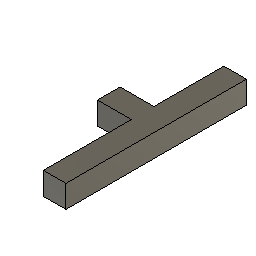
000a Full Robot (Autodesk Fusion 360 archive; units mm, degrees)
design "Top Piece"
Autodesk Fusion 360 part; units mm, degrees
sketch "Sketch1" plane through (0, 0, 0) normal (0, 0, 1) x (1, 0, 0)
  line L0 (0, -139.7) -> (0, -50.8)
  line L1 (-12.7, -50.8) -> (-12.7, -77.47)
  line L2 (-12.7, -90.17) -> (-12.7, -139.7)
  line L3 (-12.7, -90.17) -> (-31.75, -90.17)
  line L4 (-12.7, -77.47) -> (-31.75, -77.47)
  line L5 (-31.75, -90.17) -> (-31.75, -77.47)
  line L6 (-12.7, -50.8) -> (-12.7, -38.1)
  line L7 (-12.7, -38.1) -> (0, -38.1)
  line L8 (0, -38.1) -> (0, -50.8)
  line L9 (-12.7, -139.7) -> (0, -139.7)
  dimension "d7" = 19.05
  dimension "d8" = 19.05
  constraint vertical L0
  constraint perpendicular L2 L3
  constraint perpendicular L1 L4
  constraint perpendicular L4 L5
  constraint perpendicular L6 L7
  constraint perpendicular L0 L9
  measures "d7" distance of L2.start L3.end
  measures "d8" distance of L1.end L4.end
extrude "Extrude1" add sketch "Sketch1" along normal blind 12.7 makes body 1
copy_body "Body->Comp1" bodies 1 removing the originals makes body 2 in component "Component"
component "Component" placed x (1, 0, 0) y (0, 1, 0) z (0, 0, 1) at (0, 0, 0)

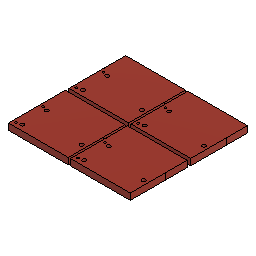
design "Gear_Motor_Base_Kevin"
Autodesk Fusion 360 part; units mm, degrees
sketch "Sketch2" plane through (0, 0, 0) normal (0, 0, 1) x (1, 0, 0)
  circle A0 centre (13.462, 0) radius 1.3075
  circle A1 centre (-23.8728, -9.6811) radius 0.7526
  circle A2 centre (-20.2417, -8.7123) radius 1.2943
  circle A3 centre (-20.2417, 8.7369) radius 1.2424
  circle A4 centre (-23.8726, 9.6996) radius 0.7649
  line L0 (-26.162, 11.1786) -> (-26.1614, 11.1786)
  line L1 (0, 0) -> (0, 0.4176)
  line L2 (-26.162, 0.0013) -> (-26.1613, 12.7013)
  line L3 (-26.162, 0.0013) -> (-26.162, -12.6987)
  line L4 (-26.162, -12.6987) -> (16.5915, -12.6998)
  line L5 (-26.1613, 12.7013) -> (16.5922, 12.7002)
  line L6 (16.5922, 12.7002) -> (16.5915, -12.6998)
  dimension "d23" = 12.7
  constraint coincident L1.start origin
  constraint perpendicular L0 L2
  constraint coincident L2 L0.end
  constraint perpendicular L4 L6
  measures "d23" distance of L2.start L2.end
extrude "Extrude2" add sketch "Sketch2" along normal blind 6.35 makes body 1
sketch "Sketch4" plane through (0, 0, 0) normal (0, 1, 0) x (1, 0, 0)
  circle A0 centre (57.912, -2.54) radius 1.1811
  circle A1 centre (37.592, -2.54) radius 1.1811
  dimension "d26" = 2.3622
  dimension "d27" = 2.3622
  dimension "d28" = 20.32
  measures "d26" diameter of A0
  measures "d27" diameter of A1
  measures "d28" distance of A0.centre A1.centre
extrude "Extrude4" cut 1 faces at (-8.6811, 0.0157, 6.35) along direction (0, 0, -1) blind 1.778 on bodies 1 bodies 1
extrude "Extrude5" add 1 faces at (-11.9102, 12.7009, 1.524) along direction (0.000026, 1, 0) blind 15.24 on bodies 1 bodies 1
move_body "Move2" bodies 1 to x (1, 0, 0) y (0, 1, 0) z (0, 0, 1) at (-17.3889, 13.7662, 0)
copy_body "CopyPasteBodies2" bodies 1 makes body 2
move_body "Move3" bodies 2 to x (1, 0, 0) y (0, 1, 0) z (0, 0, 1) at (0.1663, 43.0831, 0)
copy_body "CopyPasteBodies3" bodies 2 1 makes body 3 makes body 4
move_body "Move4" bodies 3 4 to x (1, 0, 0) y (0, 1, 0) z (0, 0, 1) at (-44.241, -0.152, 0)

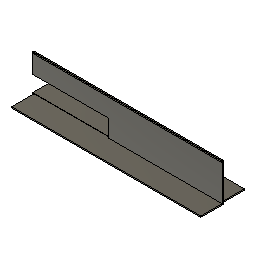
design "SideParts"
Autodesk Fusion 360 part; units mm, degrees
sketch "Sketch1" plane through (0, 0, 0) normal (1, 0, 0) x (0, 1, 0)
  line L0 (0, 0) -> (0, 39.37)
  line L1 (0, 39.37) -> (1.27, 39.37)
  line L2 (1.27, 39.37) -> (1.27, 0)
  line L3 (1.27, 0) -> (0, 0)
  line L4 (1.27, 0) -> (24.13, 0)
  line L5 (24.13, 0) -> (24.13, 1.27)
  line L6 (24.13, 1.27) -> (1.27, 1.27)
  line L7 (52.07, 0) -> (52.07, 1.27)
  line L8 (74.93, 0) -> (76.2, 0)
  line L9 (74.93, 0) -> (52.07, 0)
  line L10 (74.93, 39.37) -> (74.93, 0)
  line L11 (76.2, 39.37) -> (74.93, 39.37)
  line L12 (76.2, 0) -> (76.2, 39.37)
  line L13 (52.07, 1.27) -> (74.93, 1.27)
  point P0 (76.2, 0)
  dimension "d1" = 39.37
  dimension "d2" = 22.86
  constraint coincident L0.start L3.end
  constraint vertical L0
  constraint perpendicular L0 L1
  constraint perpendicular L1 L2
  constraint perpendicular L0 L3
  constraint perpendicular L2 L4
  constraint perpendicular L4 L5
  constraint coincident L2 L6.end
  constraint perpendicular L2 L6
  measures "d1" distance of L0.start L0.end
  measures "d2" distance of L2.end L4.end
extrude "Extrude1" add sketch "Sketch1" along normal blind 203.2 makes body 1 at (67.7333, 76.2, 13.1233) makes body 2 at (67.7333, 0, 13.1233)
sketch "Sketch2" plane through (0, 1.27, 0) normal (0, 1, 0) x (-1, 0, 0)
  line L0 (0, 1.27) -> (0, 39.37)
  line L1 (0, 39.37) -> (-203.2, 39.37)
  line L2 (-203.2, 39.37) -> (-203.2, 1.27)
  line L3 (-203.2, 1.27) -> (0, 1.27)
  line L4 (0, 1.27) -> (-81.28, 1.27)
  line L5 (-81.28, 1.27) -> (-81.28, 19.812)
  line L6 (-81.28, 19.812) -> (0.0016, 19.812)
  line L7 (0.0016, 19.812) -> (0, 1.27)
  dimension "d5" = 81.28
  dimension "d6" = 18.542
  constraint coincident L0.start L3.end
  constraint perpendicular L0 L4
  constraint perpendicular L4 L5
  constraint horizontal L6
  measures "d5" distance of L0.start L4.end
  measures "d6" distance of L4.end L5.end
extrude "Extrude2" cut sketch "Sketch2" against normal blind 12.7 contours L0 L3 L4 L5 L6 L7 bodies 2
copy_body "Body->Comp1" bodies 2 removing the originals makes body 3 in component "SidePiece"
copy_body "Body->Comp2" bodies 1 removing the originals makes body 4 in component "SidePiece (1)"
sketch "Sketch3" plane through (0, -1.4983, 0) normal (0, -1, 0) x (1, 0, 0)
  line L0 (1.7142, 39.2384) -> (1.7142, 1.1384)
  line L1 (1.7142, 1.1384) -> (204.9142, 1.1384)
  line L2 (204.9142, 1.1384) -> (204.9142, 39.2384)
  line L3 (204.9142, 39.2384) -> (1.7142, 39.2384)
  line L4 (1.7142, 1.1384) -> (82.9942, 1.1384)
  line L5 (82.9942, 1.1384) -> (82.9942, 19.6804)
  line L6 (82.9942, 19.6804) -> (1.7142, 19.6804)
  line L7 (1.7142, 19.6804) -> (1.7142, 1.1384)
  dimension "d9" = 81.28
  dimension "d10" = 18.542
  dimension "d11" = 81.28
  constraint coincident L0.end L1.start
  constraint perpendicular L0 L4
  constraint perpendicular L4 L5
  constraint perpendicular L0 L6
  measures "d9" distance of L0.end L4.end
  measures "d10" distance of L4.end L5.end
  measures "d11" distance of L5.end L6.end
extrude "Extrude1'" cut sketch "Sketch3" against normal blind 30.48 contours L0 L1 L4 L5 L6 L7 sketch seen with x (1, 0, 0) y (0, 1, 0) z (0, 0, 1) at (-1.7142, 76.4283, 0.1316) bodies 4 in component "SidePiece (1)"
component "SidePiece" placed x (1, 0, 0) y (0, 1, 0) z (0, 0, 1) at (0, 0, 0)
component "SidePiece (1)" placed x (1, 0, 0) y (0, 1, 0) z (0, 0, 1) at (1.7142, -76.4283, -0.1316)

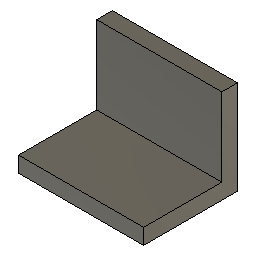
design "Bracket"
part number: 2025-11-20-12-51-07-591
Autodesk Fusion 360 part; units mm, degrees
sketch "Sketch1" plane through (0, 0, 0) normal (0, 0, 1) x (1, 0, 0)
  line L0 (0, 0) -> (0, -38.1)
  line L1 (0, -38.1) -> (-6.35, -38.1)
  line L2 (-6.35, -38.1) -> (-6.35, -6.35)
  line L3 (0, 0) -> (-38.1, 0)
  line L4 (-38.1, 0) -> (-38.1, -6.35)
  line L5 (-38.1, -6.35) -> (-6.35, -6.35)
  dimension "d1" = 38.1
  dimension "d2" = 6.35
  dimension "d3" = 31.75
  constraint coincident L0.start L3.start
  constraint vertical L0
  constraint perpendicular L0 L1
  constraint perpendicular L1 L2
  measures "d1" distance of L0.start L0.end
  measures "d2" distance of L0.end L1.end
  measures "d3" distance of L1.end L2.end
extrude "Extrude1" add sketch "Sketch1" along normal mid plane 50.8 makes body 1
copy_body "Body->Comp1" bodies 1 removing the originals makes body 2 in component "Bracket"
component "Bracket" placed x (1, 0, 0) y (0, 1, 0) z (0, 0, 1) at (0, 0, 0)
